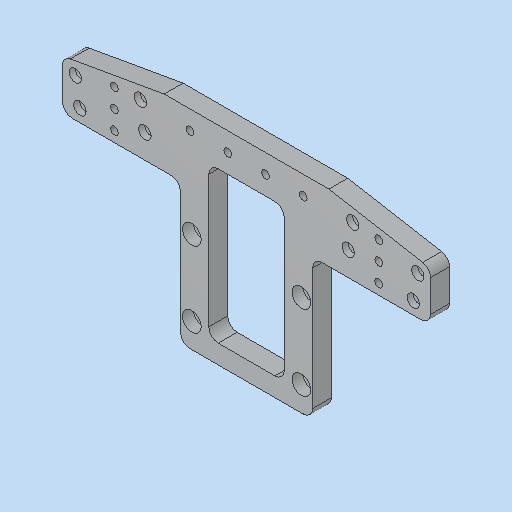
# Autodesk Inventor part: MM0948AN002_G01_115
Saved by Autodesk Inventor 2023.3 (Build 273359000, 359)
## iProperties
RuleStatus: InUse
Created: 2023-03-23
Part Number: MM0948AN002_G01_115
Material: 3.3547 AlMg4,5Mn0,7 - AW 5083
Description: =<RBPARTNOTITLE2>
Document SubType Name: Modeling
Designer: ric7an
Mass: 201.707 g
Surface Area: 286.596 cm^2
Volume: 74.7063 cm^3
Density: 2.7 g/cm^3
Appearance: Aluminium AnP
AnP_Kategorie: 1
AnP_Material: =<Material>
MaxAbmaße: 10 x 318 x 195 (FM)
AnP_TemplVers: 20200821
RBDOCUMENTTYPE: DRF
RBDOCUMENTVERSION: 00
RBDRAWINGMAINSCALE: 1:1
RBDRAWINGMISSINGSPEC: --
RBDRAWINGVOLUME: --
RBDSV1: 0850
RBGBEDGESIN1: +0,5
RBGBEDGESIN2: +0,2
RBGBEDGESOUT1: -0,3
RBGBEDGESOUT2: -0,1
RBMATERIAL: =<Material>
RBMATMEETS: --
RBMATNO: =<Part Number>
RBPARTMADEOF: 10 x 318 x 195 (FM)
RBPARTNO: SIEHE MNR
RBPARTNOTITLE1: manufactured part
RBPARTNOTITLE2: Anfertigungsteil
RBPARTSAFETYINDICATOR: --
RBSURFACE: anodised colourless
RBSURFACE2: eloxiert farblos
RBZEDGESNORM: ISO13715:2002-06
RBZGENDIMCLASS: m
RBZGENDIMNORM: ISO 2768-1:1989-11
RBZGENGEOCLASS: H
RBZGENGEONORM: ISO 2768-2:1989-11
RBZSURFACENORM: ISO13D2:2002-02
RBZTOLERANCENORM: ISO 14405-1:2010-12
AnP_Kommentar_aktuell: =<Comments>
AnP_Material_aktuell: =<Material>
Author: FH/Wi
Keywords: =<RBPARTMADEOF>
Comments: =<RBSURFACE2>
Revision Number: 01
Autodesk Inventor part; units mm, degrees
ref_plane "YZ Plane" through (0, 0, 0) normal (1, 0, 0) x (0, 1, 0)
ref_plane "XZ Plane" through (0, 0, 0) normal (0, 1, 0) x (-1, 0, 0)
ref_plane "XY Plane" through (0, 0, 0) normal (0, 0, 1) x (1, 0, 0)
sketch "Skizze1" plane through (0, 0, 0) normal (0, 0, 1) x (1, 0, 0)
  line L0 (-97.5, 0) -> (-97.5, 110)
  line L1 (-97.5, 110) -> (97.5, 110)
  line L2 (97.5, 110) -> (97.5, 0)
  line L3 (97.5, 0) -> (-97.5, 0)
  line L4 (0, 132) -> (0, -22) projected
  line L5 (-136.5, 0) -> (136.5, 0) projected
  point P0 (0, 0)
  dimension "d1" = 110
  dimension "d3" = 195
  constraints: 8 end point, 2 perpendicular, 1 collinear, 1 parallel, 1 vertical, 1 other
  measures "d1" distance between parallel lines of L3 L1
  measures "d3" distance of L0.end L1.end
extrude "Extrusion1" add sketch "Skizze1" along normal blind 10
sketch "Skizze6" plane through (0, 0, 0) normal (0, 0, -1) x (-1, 0, 0)
  line L0 (-90.74, 94.9489) -> (-88.309, 81.1616)
  line L1 (-88.309, 81.1616) -> (-53.8407, 87.2393)
  line L2 (-53.8407, 87.2393) -> (-56.2718, 101.0266)
  line L3 (-56.2718, 101.0266) -> (-90.74, 94.9489)
  line L4 (56.2718, 101.0266) -> (53.8407, 87.2393)
  line L5 (53.8407, 87.2393) -> (88.309, 81.1616)
  line L6 (88.309, 81.1616) -> (90.74, 94.9489)
  line L7 (90.74, 94.9489) -> (56.2718, 101.0266)
  line L8 (-97.5, 110) -> (97.5, 110) projected
  line L9 (0, -63.6) -> (0, 381.6) projected
  line L10 (-136.5, 0) -> (136.5, 0) projected
  line L11 (-75.624, 110) -> (-56.228, 0) construction
  line L12 (75.624, 110) -> (56.228, 0) construction
  line L13 (97.5, 0) -> (-97.5, 0) construction
  point P0 (0, 0)
  dimension "d37" = 14
  dimension "d38" = 35
  dimension "d41" = 14
  dimension "d42" = 35
  dimension "d293" = 10
  dimension "d295" = 10
  dimension "d302" = 8.9734
  dimension "d303" = 8.9734
  dimension "d304" = 75.624
  dimension "d305" = 75.624
  constraints: 20 end point, 4 parallel, 3 point on line, 2 perpendicular, 1 horizontal alignment, 2 other
  measures "d37" distance of L0.start L0.end
  measures "d38" distance of L2.end L0.start
  measures "d41" distance of L4.start L4.end
  measures "d42" distance of L4.end L5.end
  measures "d293" angle of L9 L11
  measures "d295" angle of L12 L9
  measures "d302" distance from line of L2.end L8
  measures "d303" distance from line of L4.start L8
  measures "d304" distance from line of L9 L11.start
  measures "d305" distance from line of L12.start L9
hole "Bohrung1" at (90.74, 94.9489, 0) at (56.2718, 101.0266, 0) at (53.8407, 87.2393, 0) at (88.309, 81.1616, 0) at (-56.2718, 101.0266, 0) at (-53.8407, 87.2393, 0) at (-90.74, 94.9489, 0) at (-88.309, 81.1616, 0) direction (0, 0, 1) diameter 6.6 end through all counterbore diameter 11 counterbore depth 6.8 clearance for "Inbusschraube ISO 4762  versenkt" size "M6" standard "ISO"
sketch "Skizze8" plane through (0, 0, 10) normal (0, 0, 1) x (1, 0, 0)
  line L0 (0, 381.6) -> (0, -63.6) projected
  line L1 (-97.5, 0) -> (97.5, 0) projected
  line L2 (97.5, 0) -> (97.5, 110) projected
  line L3 (97.5, 110) -> (-97.5, 110) projected
  point P0 (0, 0)
  point P1 (-29, 53)
  point P2 (-29, 13)
  point P3 (29, 53)
  point P4 (29, 13)
  point P5 (-29, 83)
  point P6 (29, 83)
  point P7 (46.4585, 318)
  point P8 (-46.4585, 318)
  dimension "d169" = 40
  dimension "d170" = 58
  dimension "d299" = 30
  dimension "d301" = 27
  constraints: 3 symmetric about line, 2 vertical alignment, 1 other
  measures "d169" distance of point (29, 53) point (29, 13)
  measures "d170" distance of point (29, 53) point (-29, 53)
  measures "d299" distance of point (29, 53) point (29, 83)
hole "Bohrung3" at (-29, 53, 10) at (29, 53, 10) at (-29, 13, 10) at (29, 13, 10) direction (0, 0, -1) diameter 5.5 end through all counterbore diameter 10 counterbore depth 5.7 clearance for "Inbusschraube ISO 4762  versenkt" size "M5" standard "ISO"
sketch "Skizze17" plane through (0, 0, 10) normal (0, 0, 1) x (1, 0, 0)
  line L0 (97.5, 110) -> (-97.5, 110) projected
  line L1 (0, 369.6) -> (0, -61.6) projected
  point P0 (0, 0)
  point P1 (70, 100)
  point P2 (70, 90)
  point P3 (70, 80)
  point P4 (-70, 100)
  point P5 (-70, 90)
  point P6 (-70, 80)
  point P7 (-30, 100)
  point P8 (-10, 100)
  point P9 (10, 100)
  point P10 (30, 100)
  dimension "d152" = 10
  dimension "d153" = 10
  dimension "d154" = 140
  dimension "d163" = 20
  dimension "d164" = 60
  dimension "d165" = 10
  dimension "d306" = 10
  constraints: 5 symmetric about line, 2 vertical alignment, 1 horizontal alignment
  measures "d152" distance of point (70, 80) point (70, 90)
  measures "d153" distance of point (70, 100) point (70, 90)
  measures "d154" distance of point (70, 100) point (-70, 100)
  measures "d163" distance of point (10, 100) point (-10, 100)
  measures "d164" distance of point (30, 100) point (-30, 100)
  measures "d165" distance from line of L0 point (-30, 100)
  measures "d306" distance from line of point (-70, 100) L0
hole "Bohrung10" at (70, 100, 10) at (70, 90, 10) at (70, 80, 10) at (-70, 100, 10) at (-70, 90, 10) at (-70, 80, 10) at (-30, 100, 10) at (-10, 100, 10) at (30, 100, 10) at (10, 100, 10) direction (0, 0, -1) diameter 4.134 end through all thread size "M5x0.8" designation "M5" class "6H" standard "ISO Metric profile"
sketch "Skizze23" plane through (0, 0, 10) normal (0, 0, 1) x (1, 0, 0)
  line L0 (-97.5, 0) -> (97.5, 0) projected
  line L1 (-97.5, 110) -> (-97.5, 0) projected
  line L2 (97.5, 110) -> (-97.5, 110) projected
  line L3 (97.5, 0) -> (97.5, 110) projected
  line L4 (-97.5, 74.5) -> (-35, 74.5)
  line L5 (-35, 74.5) -> (-35, 0)
  line L6 (-35, 0) -> (-97.5, 0)
  line L7 (-97.5, 0) -> (-97.5, 74.5)
  line L8 (35, 0) -> (97.5, 0)
  line L9 (97.5, 0) -> (97.5, 74.5)
  line L10 (97.5, 74.5) -> (35, 74.5)
  line L11 (35, 74.5) -> (35, 0)
  line L12 (20, 10) -> (-20, 10)
  line L13 (-20, 10) -> (-20, 90)
  line L14 (-20, 90) -> (20, 90)
  line L15 (20, 90) -> (20, 10)
  line L16 (0, 132) -> (0, -22) projected
  line L17 (-97.5, 100.5) -> (-43.6228, 110)
  line L18 (97.5, 100.5) -> (43.6228, 110)
  point P0 (0, 0)
  dimension "d307" = 74.5
  dimension "d308" = 74.5
  dimension "d309" = 70
  dimension "d310" = 10
  dimension "d311" = 80
  dimension "d312" = 40
  dimension "d315" = 10
  dimension "d316" = 10
  dimension "d317" = 9.5
  dimension "d318" = 9.5
  constraints: 28 end point, 8 point on line, 6 parallel, 3 horizontal, 3 perpendicular, 2 other
  measures "d307" distance of L4.end L5.end
  measures "d308" distance of L10.end L8.start
  measures "d309" distance between parallel lines of L11 L5
  measures "d310" distance between parallel lines of L0 L12
  measures "d311" distance of L14.end L12.start
  measures "d312" distance between parallel lines of L15 L13
  measures "d315" angle of L2 L17
  measures "d316" angle of L2 L18
  measures "d317" distance from line of L2 L17.start
  measures "d318" distance from line of L18.start L2
extrude "Extrusion8" cut sketch "Skizze23" against normal through all contours L1 L4 L5 L0 | L1 L2 L17 | L11 L10 L3 L0 | L16 L14 L15 L12 | L12 L13 L14 L16 | L2 L3 L18
fillet "Rundung7" radius 5 12 edges at (-20, 90, 5) (20, 90, 5) (20, 10, 5) (-20, 10, 5) (35, 74.5, 5) (-35, 74.5, 5) (-97.5, 74.5, 5) (-97.5, 100.5, 5) (97.5, 74.5, 5) (97.5, 100.5, 5) (-35, 0, 5) (35, 0, 5)
equation "\"d41\" = d37"
equation "\"d42\" = d38"
equation "\"d153\" = d152"
